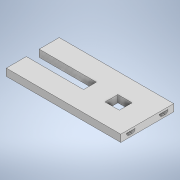
# Autodesk Inventor part: suport_lamele
Saved by Autodesk Inventor 2022.6 (Build 266554000, 554)
## iProperties
Created: 2026-03-13
Part Number: suport_lamele
Material: Generic
Document SubType Name: Modeling
Designer: Dragos Macovei
Density: 1 g/cm^3
Appearance: Default
Author: Dragos Macovei
Autodesk Inventor part; units mm, degrees
ref_plane "YZ Plane" through (0, 0, 0) normal (1, 0, 0) x (0, 1, 0)
ref_plane "XZ Plane" through (0, 0, 0) normal (0, 1, 0) x (-1, 0, 0)
ref_plane "XY Plane" through (0, 0, 0) normal (0, 0, 1) x (1, 0, 0)
sketch "Sketch1" plane through (0, 0, 0) normal (0, 1, 0) x (-1, 0, 0)
  line L0 (0, 0) -> (80, 0)
  line L1 (80, 0) -> (80, 29)
  line L2 (80, 29) -> (0, 29)
  line L3 (0, 29) -> (0, 0)
  line L4 (80, 23) -> (0, 23)
  line L5 (0, 23) -> (0, 6)
  line L6 (0, 6) -> (80, 6)
  line L7 (80, 6) -> (80, 23)
  line L8 (80, 19) -> (0, 19)
  line L9 (0, 19) -> (0, 10)
  line L10 (0, 10) -> (80, 10)
  line L11 (80, 10) -> (80, 19)
  line L12 (80, 33) -> (0, 33)
  line L13 (0, 33) -> (0, -4)
  line L14 (0, -4) -> (80, -4)
  line L15 (80, -4) -> (80, 33)
  point P0 (0, 19)
  point P1 (0, 23)
  point P2 (80, 6)
  dimension "d0" = 29
  dimension "d1" = 80
  dimension "d2" = 6
  dimension "d3" = 6
  dimension "d4" = 4
  dimension "d5" = 4
  dimension "d6" = 4
  dimension "d7" = 4
  constraints: 32 end point, 8 parallel, 4 horizontal, 4 perpendicular, 4 point on line
  measures "d0" distance of L1.end L0.end
  measures "d1" distance of L1.end L2.end
  measures "d2" distance between parallel lines of L2 L4
  measures "d3" distance between parallel lines of L0 L6
  measures "d4" distance between parallel lines of L4 L8
  measures "d5" distance between parallel lines of L6 L10
  measures "d6" distance between parallel lines of L14 L0
  measures "d7" distance between parallel lines of L2 L12
extrude "Extrusion1" add sketch "Sketch1" along normal blind 5 contours L0 L15 L14 L13 | L3 L10 L1 L6 | L3 L4 L1 L8 | L13 L12 L15 L2
sketch "Sketch2" plane through (0, 0, 23) normal (1, 0, 0) x (0, 0, -1)
  line L0 (0, 0) -> (4, 0) projected
  line L1 (4, 0) -> (4, 5) projected
  line L2 (0, 5) -> (4, 5) projected
  line L3 (0, 0) -> (0, 5) projected
  line L4 (-10, 0) -> (-6, 0) projected
  line L5 (-6, 0) -> (-6, 5) projected
  line L6 (-10, 5) -> (-6, 5) projected
  line L7 (-10, 0) -> (-10, 5) projected
  line L8 (13, 0) -> (17, 0) projected
  line L9 (17, 0) -> (17, 5) projected
  line L10 (13, 5) -> (17, 5) projected
  line L11 (13, 0) -> (13, 5) projected
  line L12 (23, 0) -> (27, 0) projected
  line L13 (27, 0) -> (27, 5) projected
  line L14 (23, 5) -> (27, 5) projected
  line L15 (23, 0) -> (23, 5) projected
  line L16 (-10, 5) -> (-6, 5) projected
  line L17 (-10, 5) -> (4, 5)
  line L18 (4, 5) -> (4, 3.5)
  line L19 (4, 3.5) -> (-10, 3.5)
  line L20 (-10, 3.5) -> (-10, 5)
  line L21 (-10, 0) -> (4, 0)
  line L22 (4, 0) -> (4, 1.5)
  line L23 (4, 1.5) -> (-10, 1.5)
  line L24 (-10, 1.5) -> (-10, 0)
  line L25 (13, 0) -> (13, 5) projected
  line L26 (27, 0) -> (27, 5) projected
  line L27 (13, 5) -> (27, 5)
  line L28 (27, 5) -> (27, 3.5)
  line L29 (27, 3.5) -> (13, 3.5)
  line L30 (13, 3.5) -> (13, 5)
  line L31 (27, 0) -> (13, 0)
  line L32 (13, 0) -> (13, 1.5)
  line L33 (13, 1.5) -> (27, 1.5)
  line L34 (27, 1.5) -> (27, 0)
  point P0 (-3, 3.5)
  point P1 (2, 0)
  point P2 (23, 1.5)
  point P3 (17, 1.5)
  point P4 (17, 0)
  point P5 (23, 0)
  point P6 (17, 3.5)
  point P7 (23, 3.5)
  point P8 (0, 1.5)
  point P9 (-6, 1.5)
  point P10 (-6, 3.5)
  point P11 (0, 3.5)
  dimension "d10" = 2
  dimension "d11" = 1.5
  dimension "d12" = 1.5
  constraints: 32 end point, 8 parallel, 6 point on line, 4 horizontal, 4 perpendicular, 2 midpoint
  measures "d10" distance from line of L23 point (-3, 3.5)
  measures "d11" distance between parallel lines of L19 L2
  measures "d12" distance from line of point (2, 0) L23
extrude "Extrusion2" add sketch "Sketch2" against normal up to surface (80 mm away) contours L21 L5 L23 L3 | L19 L5 L17 L3 | L9 L33 L15 L31 | L9 L27 L15 L29
sketch "Sketch3" plane through (0, 0, 19) normal (0, 0, -1) x (-1, 0, 0)
  line L0 (0, 3.5) -> (80, 3.5) projected
  line L1 (0, 0) -> (80, 0) projected
  line L2 (80, 0) -> (80, 5) projected
  line L3 (0, 5) -> (80, 5) projected
  line L4 (0, 0) -> (0, 5) projected
  line L5 (0, 0) -> (80, 0) projected
  line L6 (0, 5) -> (15, 5)
  line L7 (15, 5) -> (15, 0)
  line L8 (15, 0) -> (0, 0)
  line L9 (0, 0) -> (0, 5)
  line L10 (0, 5) -> (80, 5) projected
  line L11 (25, 5) -> (40, 5)
  line L12 (40, 5) -> (40, 0)
  line L13 (40, 0) -> (25, 0)
  line L14 (25, 0) -> (25, 5)
  line L15 (25, 5) -> (40, 5)
  line L16 (40, 5) -> (40, 0)
  line L17 (40, 0) -> (25, 0)
  line L18 (25, 0) -> (25, 5)
  dimension "d15" = 15
  dimension "d16" = 15
  dimension "d17" = 10
  constraints: 24 end point, 6 parallel, 3 horizontal, 3 perpendicular, 2 point on line, 1 midpoint
  measures "d15" distance of L7.end L8.end
  measures "d16" distance of L12.end L13.end
  measures "d17" distance between parallel lines of L14 L7
extrude "Extrusion3" add sketch "Sketch3" along normal up to next contours L4 L3 L7 L0 | L0 L7 L1 L4 | L14 L3 L12 L0 | L0 L12 L1 L14
fillet "Fillet1" radius 2 4 edges at (-40, 1.5, 6) (-40, 1.5, 0) (-40, 1.5, 23) (-40, 1.5, 29)
body "Solid1"
